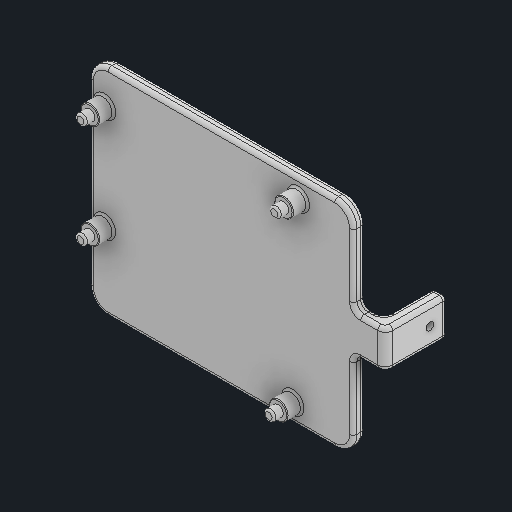
# Autodesk Inventor part: arduino_alusta
Saved by Autodesk Inventor 2026.1 (Build 301233020, 233B)
## iProperties
Created: 2025-10-28
Part Number: arduino_alusta
Material: Generic
Document SubType Name: Modeling
Designer: amon-
Density: 1 g/cm^3
Appearance: Default
Author: amon-
Autodesk Inventor part; units mm, degrees
ref_plane "YZ Plane" through (0, 0, 0) normal (1, 0, 0) x (0, 1, 0)
ref_plane "XZ Plane" through (0, 0, 0) normal (0, 1, 0) x (-1, 0, 0)
ref_plane "XY Plane" through (0, 0, 0) normal (0, 0, 1) x (1, 0, 0)
sketch "Sketch1" plane through (0, 0, 0) normal (0, 0, 1) x (1, 0, 0)
  line L0 (-35.5, -29) -> (35.5, -29)
  line L1 (35.5, -29) -> (35.5, 29)
  line L2 (35.5, 29) -> (-35.5, 29)
  line L3 (-35.5, 29) -> (-35.5, -29)
  line L4 (-35.5, -29) -> (35.5, 29) construction
  line L5 (35.5, -29) -> (-35.5, 29) construction
  circle A0 centre (-31.5, 19.5) radius 1.4
  circle A1 centre (-31.5, -8.44) radius 1.4
  circle A2 centre (20.7, 24) radius 1.4
  circle A3 centre (19.22, -24.1) radius 1.4
  circle A4 centre (-31.5, -8.44) radius 2.5
  circle A5 centre (-31.5, 19.5) radius 2.5
  circle A6 centre (20.7, 24) radius 2.5
  circle A7 centre (19.22, -24.1) radius 2.5
  line L6 (-51.42, 0) -> (60.02, 0) projected
  line L7 (35.5, 5) -> (40.6, 5)
  line L8 (40.6, 5) -> (40.6, -5)
  line L9 (40.6, -5) -> (35.5, -5)
  line L10 (40.6, 5) -> (44.1, 5)
  line L11 (44.1, 5) -> (44.1, -5)
  line L12 (44.1, -5) -> (40.6, -5)
  line L13 (40.6, -5) -> (40.6, 5)
  point P0 (0, 0)
  point P1 (40.6, -5)
  dimension "d0" = 71
  dimension "d1" = 58
  dimension "d6" = 4
  dimension "d7" = 27.94
  dimension "d8" = 2.8
  dimension "d9" = 9.5
  dimension "d10" = 52.2
  dimension "d11" = 5
  dimension "d12" = 4.9
  dimension "d13" = 1.48
  dimension "d16" = 5
  dimension "d29" = 5.1
  dimension "d30" = 10
  dimension "d31" = 10
  dimension "d32" = 3.5
  constraints: 26 end point, 8 centre point, 6 equal radius, 5 perpendicular, 4 coincident, 4 parallel, 2 horizontal, 2 midpoint, 2 point on line, 1 vertical alignment, 1 other
  measures "d0" distance between parallel lines of L1 L3
  measures "d1" distance between parallel lines of L0 L2
  measures "d6" distance from line of L3 A0.centre
  measures "d7" distance of A0.centre A1.centre
  measures "d8" diameter of A0
  measures "d9" distance from line of L2 A0.centre
  measures "d10" horizontal distance of A2.centre A0.centre
  measures "d11" distance from line of L2 A2.centre
  measures "d12" distance from line of L0 A3.centre
  measures "d13" horizontal distance of A3.centre A2.centre
  measures "d16" diameter of A5
  measures "d29" distance of L7.start L7.end
  measures "d30" distance of L7.end L8.end
  measures "d31" distance of L10.end L11.end
  measures "d32" distance of L11.end L12.end
extrude "Extrusion1" add sketch "Sketch1" along normal mid plane 3 contours L3 L6 L1 L0 | L3 L2 L1 L6 | A0 | A1 | A2 | A3 | A4 | A5 | A6 | A7
fillet "Fillet1" radius 5 4 edges at (-35.5, 29, 0) (35.5, 29, 0) (35.5, -29, 0) (-35.5, -29, 0)
extrude "Extrusion2" add sketch "Sketch1" along normal blind 8 contours A0 | A1 | A2 | A3
extrude "Extrusion3" add sketch "Sketch1" along normal blind 5.5 contours A0 | A1 | A2 | A3 | A4 | A5 | A6 | A7
fillet "Fillet3" radius 0.5 8 edges at (-32.9, 19.5, 8) (-32.9, -8.44, 8) (19.3, 24, 8) (17.82, -24.1, 8) (16.72, -24.1, 1.5) (-34, -8.44, 1.5) (-34, 19.5, 1.5) (18.2, 24, 1.5)
fillet "Fillet3" radius 0.2 4 edges at (-34, -8.44, 5.5) (16.72, -24.1, 5.5) (18.2, 24, 5.5) (-34, 19.5, 5.5)
extrude "Extrusion5" add sketch "Sketch1" along normal mid plane 3 contours L1 L6 L8 L9 | L1 L7 L8 L6
extrude "Extrusion6" add sketch "Sketch1" along normal blind 1.5 and the other way blind 15 contours L8 L6 L11 L12 | L8 L10 L11 L6
sketch "Sketch2" plane through (0, 0, -1.5) normal (0, 0, -1) x (-1, 0, 0)
  circle A0 centre (39.2436, 0) radius 80
  point P0 (0, 0)
  point P1 (-40.6, 5)
  point P2 (-40.6, -5)
  dimension "d39" = 160
  constraints: 2 point on circle, 1 centre point
  measures "d39" diameter of A0
extrude "Extrusion7" cut sketch "Sketch2" along normal through all
sketch "Sketch4" plane through (44.1, -5, 1.5) normal (1, 0, 0) x (0, 0, -1)
  line L0 (16.5, 10) -> (16.5, 0) projected
  point P0 (1.5, 5)
  point P1 (12, 5)
  dimension "d46" = 4.5
  constraints: 1 horizontal alignment
  measures "d46" distance from line of L0 point (12, 5)
hole "Hole1" at (44.1, 0, -10.5) direction (-1, 0, 0) diameter 2 end through all
fillet "Fillet6" radius 2 4 edges at (35.5, 5, 0) (35.5, -5, 0) (40.7564, 0, -1.5) (44.1, 0, 1.5)
fillet "Fillet7" radius 1 32 edges at (44.1, -5, -7.75) (35.5, -15.5, 1.5) (34.0355, -27.5355, 1.5) (0, -29, 1.5) (-34.0355, -27.5355, 1.5) (-35.5, 0, 1.5) (-34.0355, 27.5355, 1.5) (0, 29, 1.5) (34.0355, 27.5355, 1.5) (35.5, 15.5, 1.5) (39.8, 5, 1.5) (44.1, 5, -7.75) (39.8, -5, 1.5) (34.0355, -27.5355, -1.5) (0, -29, -1.5) (-34.0355, -27.5355, -1.5) (-35.5, 0, -1.5) (-34.0355, 27.5355, -1.5) (0, 29, -1.5) (34.0355, 27.5355, -1.5) (35.5, 15.5, -1.5) (38.048, 5, -1.5) (40.0125, 5, -2.0852) (40.6, 5, -9.25) (38.048, -5, -1.5) (40.0125, -5, -2.0852) (40.6, -5, -9.25) (35.5, -15.5, -1.5) (40.7564, 0, -15) (44.1, 0, -15) (42.35, -5, -15) (42.35, 5, -15)
body "Solid1"
